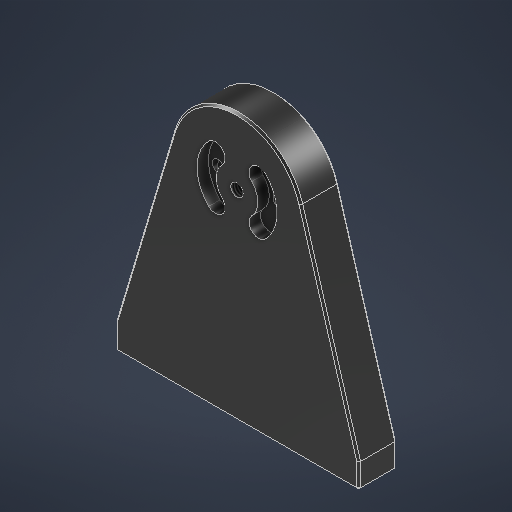
# Autodesk Inventor part: Flywheel Stand
Saved by Autodesk Inventor 2026.3 (Build 303398000, 398)
## iProperties
Created: 2026-11-01
Part Number: Flywheel Stand
Material: Steel
Document SubType Name: Modeling
Designer: ADMIN
Density: 7.85 g/cm^3
Appearance: Glossy - Black
Author: ADMIN
Autodesk Inventor part; units mm, degrees
ref_plane "YZ Plane" through (0, 0, 0) normal (1, 0, 0) x (0, 1, 0)
ref_plane "XZ Plane" through (0, 0, 0) normal (0, 1, 0) x (-1, 0, 0)
ref_plane "XY Plane" through (0, 0, 0) normal (0, 0, 1) x (1, 0, 0)
sketch "Sketch1" plane through (0, 0, 0) normal (0, 0, 1) x (1, 0, 0)
  arc A0 (16.7683, 57.5073) -> (-16.7683, 57.5073) centre (0, 52.5) ccw
  line L0 (-32, 6.5) -> (-32, 0)
  line L1 (-32, 0) -> (32, 0)
  line L2 (32, 0) -> (32, 6.5)
  line L3 (32, 6.5) -> (16.7683, 57.5073)
  line L4 (-32, 6.5) -> (-16.7683, 57.5073)
  point P0 (0, 0)
  point P1 (0, 0)
  dimension "d0" = 35
  dimension "d1" = 64
  dimension "d2" = 6.5
  dimension "d3" = 52.5
  constraints: 10 end point, 2 perpendicular, 2 point on circle, 2 tangent, 1 centre point, 1 coincident, 1 midpoint, 1 parallel, 1 vertical, 1 vertical alignment
  measures "d0" diameter of A0
  measures "d1" distance of L0.end L1.end
  measures "d2" distance of L1.end L2.end
  measures "d3" distance from line of L1 A0.centre
extrude "Extrusion1" add sketch "Sketch1" along normal mid plane 10
sketch "Sketch2" plane through (0, 0, 5) normal (0, 0, 1) x (1, 0, 0)
  arc A0 (16.7683, 57.5073) -> (-16.7683, 57.5073) centre (0, 52.5) ccw projected
  line L0 (0, 70) -> (0, 0) construction
  arc A1 (-3.8891, 56.3891) -> (-7.4246, 59.9246) centre (-5.6569, 58.1569) ccw
  arc A2 (-7.4246, 45.0754) -> (-3.8891, 48.6109) centre (-5.6569, 46.8431) ccw
  arc A3 (0, 60.5) -> (0, 44.5) centre (0, 52.5) ccw construction
  arc A4 (-7.4246, 59.9246) -> (-7.4246, 45.0754) centre (0, 52.5) ccw
  arc A5 (-3.8891, 56.3891) -> (-3.8891, 48.6109) centre (0, 52.5) ccw
  dimension "d6" = 5
  dimension "d7" = 5
  dimension "d8" = 16
  constraints: 11 point on circle, 5 centre point, 3 coincident, 2 end point, 2 point on line, 2 tangent, 1 vertical, 2 other
  measures "d6" diameter of A1
  measures "d7" diameter of A2
  measures "d8" diameter of A3
extrude "Extrusion2" cut sketch "Sketch2" against normal blind 3
mirror "Mirror1" about plane through (0, 0, 0) normal (1, 0, 0) of "Extrusion2"
sketch "Sketch3" plane through (0, 0, 5) normal (0, 0, 1) x (1, 0, 0)
  arc A0 (16.7683, 57.5073) -> (-16.7683, 57.5073) centre (0, 52.5) ccw projected
  point P0 (0, 0)
  constraints: 1 coincident
hole "Hole1" at (0, 52.5, 5) direction (0, 0, -1) diameter 3.242 end through all thread size "M4x0.7" class "6H" standard "ANSI Metric M Profile"
sketch "Sketch4" plane through (0, 0, 2) normal (0, 0, 1) x (1, 0, 0)
  circle A0 centre (0, 52.5) radius 1.621 projected
  point P0 (0, 0)
  point P1 (-8, 52.5)
  dimension "d21" = 8
  constraints: 1 horizontal alignment
  measures "d21" distance of A0.centre point (-8, 52.5)
hole "Hole2" at (-8, 52.5, 2) direction (0, 0, -1) diameter 3 depth 5
mirror "Mirror2" about plane through (0, 0, 0) normal (1, 0, 0) of "Hole2"
sketch "Sketch5" plane through (-32, 0, 5) normal (0, -1, 0) x (1, 0, 0)
  line L0 (0, 0) -> (64, 0) projected
  line L1 (32, 0) -> (32, -10) construction
  line L2 (64, -10) -> (0, -10) projected
  point P0 (32, -5)
  point P1 (24, -5)
  point P2 (40, -5)
  point P3 (32, -5)
  dimension "d29" = 16
  constraints: 3 midpoint, 2 end point, 1 horizontal alignment, 1 symmetric about line
  measures "d29" diameter of point (24, -5) L1
hole "Hole3" at (-8, 0, 0) at (8, 0, 0) direction (0, 1, 0) diameter 3 depth 54
sketch "Sketch6" plane through (-32, 0, 5) normal (0, -1, 0) x (1, 0, 0)
  line L0 (0, 0) -> (64, 0) projected
  line L1 (32, 0) -> (32, -10) construction
  line L2 (64, -10) -> (0, -10) projected
  point P0 (32, -5)
  point P1 (10, -5)
  point P2 (54, -5)
  point P3 (32, -5)
  dimension "d37" = 44
  constraints: 3 midpoint, 2 end point, 1 horizontal alignment, 1 symmetric about line
  measures "d37" diameter of point (10, -5) L1
hole "Hole4" at (-22, 0, 0) at (22, 0, 0) direction (0, 1, 0) diameter 3.242 depth 11.8 thread size "M4x0.7" class "6H" standard "ANSI Metric M Profile"
chamfer "Chamfer1" distance 0.5 angle 45 14 edges at (-24.3842, 32.0037, 5) (0, 70, 5) (24.3842, 32.0037, 5) (-24.3842, 32.0037, -5) (0, 70, -5) (24.3842, 32.0037, -5) (0, 0, 5) (0, 0, -5) (-32, 3.25, 5) (-32, 3.25, -5) (32, 3.25, -5) (32, 3.25, 5) (-32, 0, 0) (32, 0, 0)
body "Solid1"
